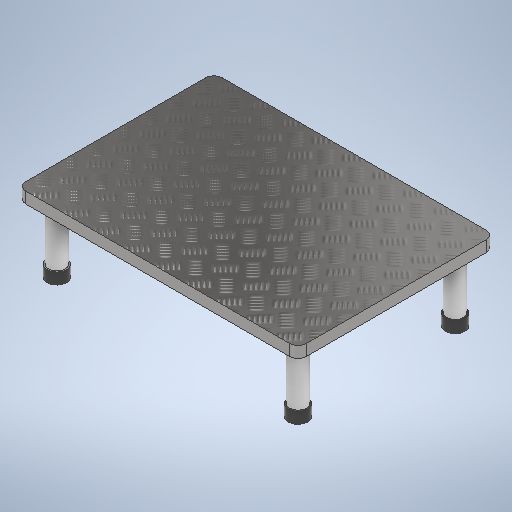
# Autodesk Inventor part: BASE
Saved by Autodesk Inventor 2025 (Build 290162000, 162)
## iProperties
Created: 2026-09-28
Part Number: BASE
Material: Aluminum
Document SubType Name: Modeling
Designer: 34275214862
Density: 2.7 g/cm^3
Appearance: Satin
Author: 34275214862
Autodesk Inventor part; units mm, degrees
ref_plane "YZ Plane" through (0, 0, 0) normal (1, 0, 0) x (0, 1, 0)
ref_plane "XZ Plane" through (0, 0, 0) normal (0, 1, 0) x (-1, 0, 0)
ref_plane "XY Plane" through (0, 0, 0) normal (0, 0, 1) x (1, 0, 0)
sketch "Sketch1" plane through (0, 0, 0) normal (0, 1, 0) x (-1, 0, 0)
  line L0 (-235, 175) -> (235, 175)
  line L1 (250, 160) -> (250, -160)
  line L2 (235, -175) -> (-235, -175)
  line L3 (-250, -160) -> (-250, 160)
  line L4 (-250, 175) -> (250, -175) construction
  line L5 (250, 175) -> (-250, -175) construction
  arc A0 (235, -175) -> (250, -160) centre (235, -160) ccw
  arc A1 (-250, -160) -> (-235, -175) centre (-235, -160) ccw
  arc A2 (-235, 175) -> (-250, 160) centre (-235, 160) ccw
  arc A3 (250, 160) -> (235, 175) centre (235, 160) ccw
  point P0 (0, 0)
  dimension "d0" = 500
  dimension "d1" = 350
  dimension "d2" = 15
  constraints: 12 end point, 8 point on circle, 8 point on line, 8 tangent, 4 centre point, 3 equal radius, 2 midpoint, 2 parallel, 1 horizontal, 1 perpendicular
  measures "d0" distance of L4.end L5.end
  measures "d1" distance of L5.start L4.end
  measures "d2" radius of A0
extrude "Extrusion1" add sketch "Sketch1" along normal blind 20
sketch "Sketch2" plane through (0, 0, 0) normal (0, -1, 0) x (1, 0, 0)
  circle A0 centre (-215, 140) radius 15
  line L0 (-235, 175) -> (235, 175) projected
  line L1 (-250, -160) -> (-250, 160) projected
  point P0 (0, 0)
  dimension "d5" = 30
  dimension "d6" = 35
  dimension "d7" = 35
  constraints: 1 centre point
  measures "d5" diameter of A0
  measures "d6" distance from line of A0.centre L0
  measures "d7" distance from line of A0.centre L1
extrude "Extrusion2" add sketch "Sketch2" along normal blind 120
sketch "Sketch3" plane through (-215, -120, 140) normal (0, -1, 0) x (1, 0, 0)
  circle A0 centre (0, 0) radius 15 projected
  circle A1 centre (0, 0) radius 17.5
  point P0 (215, -140)
  dimension "d12" = 35
  constraints: 1 centre point, 1 coincident
  measures "d12" diameter of A1
extrude "Extrusion3" add sketch "Sketch3" against normal blind 20
pattern_linear "Rectangular Pattern1" count 2 spacing 430 along (1, 0, 0) count 2 spacing 280 along (0, 0, -1) of "Extrusion2", "Extrusion3"
equation "\"d7\" = d6"
body "Solid1"
